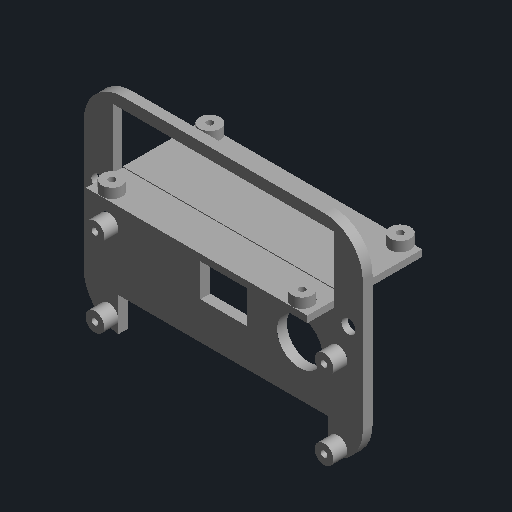
# Autodesk Inventor part: Torso_atras_B
Saved by Autodesk Inventor 2027 (Build 310192060, 192F)
## iProperties
Part Number: Torso_atras_B
Material: Genérico
Document SubType Name: Modelado
Designer: rodri
Appearance: Por defecto
Mass: 7.18882 g
Surface Area: 84.3919 cm^2
Volume: 7.18882 cm^3
Density: 1 g/cm^3
Author: rodri
Autodesk Inventor part; units mm, degrees
ref_plane "Plano de trabajo1" through (0, 0, -5.9) normal (0, 0, 1) x (1, 0, 0)
sketch "Boceto1" plane through (0, 0, -5.9) normal (0, 0, 1) x (1, 0, 0)
  line L0 (-34, 7) -> (34, 7)
  line L1 (34, 7) -> (34, 57.7)
  line L2 (34, 57.7) -> (-34, 57.7)
  line L3 (-34, 57.7) -> (-34, 7)
  constraints: 8 end point, 2 parallel, 1 horizontal, 1 perpendicular
extrude "Extrusión1" add sketch "Boceto1" along normal blind 2.4
ref_plane "Plano de trabajo2" through (0, 0, -6) normal (0, 0, 1) x (1, 0, 0)
sketch "Boceto2" plane through (0, 0, -6) normal (0, 0, 1) x (1, 0, 0)
  line L0 (-25.6, 6.7) -> (25.6, 6.7)
  line L1 (25.6, 6.7) -> (25.6, 15.3)
  line L2 (25.6, 15.3) -> (-25.6, 15.3)
  line L3 (-25.6, 15.3) -> (-25.6, 6.7)
  constraints: 8 end point, 2 parallel, 1 horizontal, 1 perpendicular
extrude "Extrusión2" cut sketch "Boceto2" along normal blind 2.6
ref_plane "Plano de trabajo3" through (0, 0, -6) normal (0, 0, 1) x (1, 0, 0)
sketch "Boceto3" plane through (0, 0, -6) normal (0, 0, 1) x (1, 0, 0)
  line L0 (-5.6, 24.4) -> (5.7, 24.4)
  line L1 (5.7, 24.4) -> (5.7, 32.7)
  line L2 (5.7, 32.7) -> (-5.6, 32.7)
  line L3 (-5.6, 32.7) -> (-5.6, 24.4)
  constraints: 8 end point, 2 parallel, 1 horizontal, 1 perpendicular
extrude "Extrusión3" cut sketch "Boceto3" along normal blind 2.6
ref_plane "Plano de trabajo4" through (0, 0, -6) normal (0, 0, 1) x (1, 0, 0)
sketch "Boceto4" plane through (0, 0, -6) normal (0, 0, 1) x (1, 0, 0)
  circle A0 centre (18.62, 27.49) radius 5.515
  constraints: 1 centre point
extrude "Extrusión4" cut sketch "Boceto4" along normal blind 2.6
ref_plane "Plano de trabajo5" through (0, 0, -3.51) normal (0, 0, 1) x (1, 0, 0)
sketch "Boceto5" plane through (0, 0, -3.51) normal (0, 0, 1) x (1, 0, 0)
  circle A0 centre (27.94, 10.175) radius 2.3
  circle A1 centre (27.94, 29.225) radius 2.3
  circle A2 centre (-27.94, 10.175) radius 2.3
  circle A3 centre (-27.94, 29.225) radius 2.3
  constraints: 4 centre point
extrude "Extrusión5" add sketch "Boceto5" along normal blind 3.41
ref_plane "Plano de trabajo6" through (0, 0, -4.9) normal (0, 0, 1) x (1, 0, 0)
sketch "Boceto6" plane through (0, 0, -4.9) normal (0, 0, 1) x (1, 0, 0)
  circle A0 centre (27.94, 10.175) radius 0.8
  circle A1 centre (27.94, 29.225) radius 0.8
  circle A2 centre (-27.94, 10.175) radius 0.8
  circle A3 centre (-27.94, 29.225) radius 0.8
  constraints: 4 centre point
extrude "Extrusión6" cut sketch "Boceto6" along normal blind 4.9
ref_plane "Plano de trabajo7" through (0, 0, -25) normal (0, 0, 1) x (1, 0, 0)
sketch "Boceto7" plane through (0, 0, -25) normal (0, 0, 1) x (1, 0, 0)
  line L0 (-27, 38.9) -> (27, 38.9)
  line L1 (27, 38.9) -> (27, 40.5)
  line L2 (27, 40.5) -> (-27, 40.5)
  line L3 (-27, 40.5) -> (-27, 38.9)
  constraints: 8 end point, 2 parallel, 1 horizontal, 1 perpendicular
extrude "Extrusión7" add sketch "Boceto7" along normal blind 28
ref_plane "Plano de trabajo8" through (0, 40.49, 0) normal (0, 1, 0) x (-1, 0, 0)
sketch "Boceto8" plane through (0, 40.49, 0) normal (0, 1, 0) x (-1, 0, 0)
  circle A0 centre (-23.2, 0.46) radius 2.5
  circle A1 centre (-23.2, -23.44) radius 2.5
  circle A2 centre (23.2, 0.46) radius 2.5
  circle A3 centre (23.2, -23.44) radius 2.5
  constraints: 4 centre point
extrude "Extrusión8" add sketch "Boceto8" along normal blind 2.39
ref_plane "Plano de trabajo9" through (0, 38.8, 0) normal (0, 1, 0) x (-1, 0, 0)
sketch "Boceto9" plane through (0, 38.8, 0) normal (0, 1, 0) x (-1, 0, 0)
  circle A0 centre (-23.2, 0.46) radius 0.8
  circle A1 centre (-23.2, -23.44) radius 0.8
  circle A2 centre (23.2, 0.46) radius 0.8
  circle A3 centre (23.2, -23.44) radius 0.8
  constraints: 4 centre point
extrude "Extrusión9" cut sketch "Boceto9" along normal blind 4.18
ref_plane "Plano de trabajo10" through (0, 0, -6) normal (0, 0, 1) x (1, 0, 0)
sketch "Boceto10" plane through (0, 0, -6) normal (0, 0, 1) x (1, 0, 0)
  line L0 (-27, 40.3) -> (27, 40.3)
  line L1 (27, 40.3) -> (27, 55)
  line L2 (27, 55) -> (-27, 55)
  line L3 (-27, 55) -> (-27, 40.3)
  constraints: 8 end point, 2 parallel, 1 horizontal, 1 perpendicular
extrude "Extrusión10" cut sketch "Boceto10" along normal blind 2.6
ref_plane "Plano de trabajo11" through (0, 0, -6) normal (0, 0, 1) x (1, 0, 0)
sketch "Boceto11" plane through (0, 0, -6) normal (0, 0, 1) x (1, 0, 0)
  circle A0 centre (30.5, 36.7) radius 1.7
  circle A1 centre (-30.5, 36.7) radius 1.7
  constraints: 2 centre point
extrude "Extrusión11" cut sketch "Boceto11" along normal blind 2.6
ref_plane "Plano de trabajo12" through (0, 0, -6) normal (0, 0, 1) x (1, 0, 0)
sketch "Boceto12" plane through (0, 0, -6) normal (0, 0, 1) x (1, 0, 0)
  circle A0 centre (30.5, 36.7) radius 2.9
  circle A1 centre (-30.5, 36.7) radius 2.9
  constraints: 2 centre point
extrude "Extrusión12" cut sketch "Boceto12" along normal blind 1
ref_plane "Plano de trabajo13" through (0, 0, 0) normal (0, 1, 0) x (0, 0, 1)
ref_plane "Plano de trabajo14" through (0, 0, 0) normal (1, 0, 0) x (0, 0, -1)
fillet "Empalme1" radius 9.5 4 edges at (34, 57.7, -4.7) (-34, 57.7, -4.7) (-34, 7, -4.7) (34, 7, -4.7)
ref_plane "Plano de trabajo15" through (0, 0, 0) normal (0, 1, 0) x (0, 0, 1)
ref_plane "Plano de trabajo16" through (0, 0, 0) normal (1, 0, 0) x (0, 0, -1)
ref_plane "Plano de trabajo17" through (0, 0, 0) normal (0, 1, 0) x (0, 0, 1)
ref_plane "Plano de trabajo18" through (0, 0, 0) normal (1, 0, 0) x (0, 0, -1)
ref_plane "Plano de trabajo19" through (0, 0, 0) normal (0, 1, 0) x (0, 0, 1)
ref_plane "Plano de trabajo20" through (0, 0, 0) normal (1, 0, 0) x (0, 0, -1)
ref_plane "Plano de trabajo21" through (0, 0, 0) normal (0, 1, 0) x (0, 0, 1)
ref_plane "Plano de trabajo22" through (0, 0, 0) normal (1, 0, 0) x (0, 0, -1)
ref_plane "Plano de trabajo23" through (0, 0, 0) normal (0, 1, 0) x (0, 0, 1)
ref_plane "Plano de trabajo24" through (0, 0, 0) normal (1, 0, 0) x (0, 0, -1)
ref_plane "Plano de trabajo25" through (0, 0, 0) normal (0, 1, 0) x (0, 0, 1)
ref_plane "Plano de trabajo26" through (0, 0, 0) normal (1, 0, 0) x (0, 0, -1)
ref_plane "Plano de trabajo27" through (0, 0, 0) normal (0, 1, 0) x (0, 0, 1)
ref_plane "Plano de trabajo28" through (0, 0, 0) normal (1, 0, 0) x (0, 0, -1)
ref_plane "Plano de trabajo29" through (0, 0, 0) normal (0, 1, 0) x (0, 0, 1)
ref_plane "Plano de trabajo30" through (0, 0, 0) normal (1, 0, 0) x (0, 0, -1)
ref_plane "Plano de trabajo31" through (0, 0, 0) normal (0, 1, 0) x (0, 0, 1)
ref_plane "Plano de trabajo32" through (0, 0, 0) normal (1, 0, 0) x (0, 0, -1)
ref_plane "Plano de trabajo33" through (0, 0, 0) normal (0, 1, 0) x (0, 0, 1)
ref_plane "Plano de trabajo34" through (0, 0, 0) normal (1, 0, 0) x (0, 0, -1)
ref_plane "Plano de trabajo35" through (0, 0, 0) normal (0, 1, 0) x (0, 0, 1)
ref_plane "Plano de trabajo36" through (0, 0, 0) normal (1, 0, 0) x (0, 0, -1)
ref_plane "Plano de trabajo37" through (0, 0, 0) normal (0, 1, 0) x (0, 0, 1)
ref_plane "Plano de trabajo38" through (0, 0, 0) normal (1, 0, 0) x (0, 0, -1)
